Autodesk Fusion 360 part; units mm, degrees
(part 2 of 5)
sketch "rib pocket (9) (2)" plane through (0, 38.2, 0) normal (0, 1, 0) x (1, 0, 0) in component "Gripper finger L (TPU)"
  line L0 (-9.25, 2.8) -> (-0.75, 2.8)
  line L1 (-0.75, 2.8) -> (-4.75, 9.6313)
  line L2 (-4.75, 9.6313) -> (-9, 11.3821)
  line L3 (-9, 11.3821) -> (-13.25, 13.0725)
  line L4 (-13.25, 13.0725) -> (-9.25, 2.8)
extrude "rib pocket (10)'" cut sketch "rib pocket (9) (2)" along normal blind 22 bodies 12 in component "Gripper finger L (TPU)"
sketch "tongue slot (2)" plane through (0, 39.2, 0) normal (0, 1, 0) x (1, 0, 0) in component "Gripper finger L (TPU)"
  line L0 (-121, 13.7) -> (-107.8, 13.7)
  line L1 (-107.8, 13.7) -> (-107.8, 5.3)
  line L2 (-107.8, 5.3) -> (-121, 5.3)
  line L3 (-121, 5.3) -> (-121, 13.7)
extrude "tongue slot (1)'" cut sketch "tongue slot (2)" along normal blind 6.4 bodies 12 in component "Gripper finger L (TPU)"
ref_plane "WorkPlane3" through (0, 44.9, 0) normal (0, 1, 0) x (0, 0, 1) in component "Gripper finger L (TPU)"
sketch "screw hole (7)" plane through (0, 44.9, 0) normal (0, 1, 0) x (1, 0, 0) in component "Gripper finger L (TPU)"
  circle A0 centre (-114, 9.5) radius 1.7
extrude "screw hole (1)''" cut sketch "screw hole (7)" along normal blind 15.3 bodies 12 in component "Gripper finger L (TPU)"
ref_plane "WorkPlane1" through (0, 33, 0) normal (0, 1, 0) x (0, 0, 1) in component "Gripper head plate (printed)"
sketch "plate" plane through (0, 33, 0) normal (0, 1, 0) x (1, 0, 0) in component "Gripper head plate (printed)"
  line L0 (-128, -23) -> (-128.1363, -24.0353)
  line L1 (-128.1363, -24.0353) -> (-128.5359, -25)
  line L2 (-128.5359, -25) -> (-129.1716, -25.8284)
  line L3 (-129.1716, -25.8284) -> (-130, -26.4641)
  line L4 (-130, -26.4641) -> (-130.9647, -26.8637)
  line L5 (-130.9647, -26.8637) -> (-132, -27)
  line L6 (-132, -27) -> (-152, -27)
  line L7 (-152, -27) -> (-153.0353, -26.8637)
  line L8 (-153.0353, -26.8637) -> (-154, -26.4641)
  line L9 (-154, -26.4641) -> (-154.8284, -25.8284)
  line L10 (-154.8284, -25.8284) -> (-155.4641, -25)
  line L11 (-155.4641, -25) -> (-155.8637, -24.0353)
  line L12 (-155.8637, -24.0353) -> (-156, -23)
  line L13 (-156, -23) -> (-156, 23)
  line L14 (-156, 23) -> (-155.8637, 24.0353)
  line L15 (-155.8637, 24.0353) -> (-155.4641, 25)
  line L16 (-155.4641, 25) -> (-154.8284, 25.8284)
  line L17 (-154.8284, 25.8284) -> (-154, 26.4641)
  line L18 (-154, 26.4641) -> (-153.0353, 26.8637)
  line L19 (-153.0353, 26.8637) -> (-152, 27)
  line L20 (-152, 27) -> (-132, 27)
  line L21 (-132, 27) -> (-130.9647, 26.8637)
  line L22 (-130.9647, 26.8637) -> (-130, 26.4641)
  line L23 (-130, 26.4641) -> (-129.1716, 25.8284)
  line L24 (-129.1716, 25.8284) -> (-128.5359, 25)
  line L25 (-128.5359, 25) -> (-128.1363, 24.0353)
  line L26 (-128.1363, 24.0353) -> (-128, 23)
  line L27 (-128, 23) -> (-128, -23)
extrude "plate (1)" add sketch "plate" along normal blind 6 separate body makes body 13 in component "Gripper head plate (printed)"
sketch "spring lug" plane through (0, 33, 0) normal (0, 1, 0) x (1, 0, 0) in component "Gripper head plate (printed)"
  line L0 (-124, -30.5) -> (-124.0852, -31.147)
  line L1 (-124.0852, -31.147) -> (-124.3349, -31.75)
  line L2 (-124.3349, -31.75) -> (-124.7322, -32.2678)
  line L3 (-124.7322, -32.2678) -> (-125.25, -32.6651)
  line L4 (-125.25, -32.6651) -> (-125.853, -32.9148)
  line L5 (-125.853, -32.9148) -> (-126.5, -33)
  line L6 (-126.5, -33) -> (-130.5, -33)
  line L7 (-130.5, -33) -> (-131.147, -32.9148)
  line L8 (-131.147, -32.9148) -> (-131.75, -32.6651)
  line L9 (-131.75, -32.6651) -> (-132.2678, -32.2678)
  line L10 (-132.2678, -32.2678) -> (-132.6651, -31.75)
  line L11 (-132.6651, -31.75) -> (-132.9148, -31.147)
  line L12 (-132.9148, -31.147) -> (-133, -30.5)
  line L13 (-133, -30.5) -> (-133, -23.5)
  line L14 (-133, -23.5) -> (-132.9148, -22.853)
  line L15 (-132.9148, -22.853) -> (-132.6651, -22.25)
  line L16 (-132.6651, -22.25) -> (-132.2678, -21.7322)
  line L17 (-132.2678, -21.7322) -> (-131.75, -21.3349)
  line L18 (-131.75, -21.3349) -> (-131.147, -21.0852)
  line L19 (-131.147, -21.0852) -> (-130.5, -21)
  line L20 (-130.5, -21) -> (-126.5, -21)
  line L21 (-126.5, -21) -> (-125.853, -21.0852)
  line L22 (-125.853, -21.0852) -> (-125.25, -21.3349)
  line L23 (-125.25, -21.3349) -> (-124.7322, -21.7322)
  line L24 (-124.7322, -21.7322) -> (-124.3349, -22.25)
  line L25 (-124.3349, -22.25) -> (-124.0852, -22.853)
  line L26 (-124.0852, -22.853) -> (-124, -23.5)
  line L27 (-124, -23.5) -> (-124, -30.5)
extrude "spring lug (1)" add sketch "spring lug" along normal blind 6 separate body makes body 14 in component "Gripper head plate (printed)"
ref_plane "WorkPlane2" through (0, 0, 14.5) normal (0, 0, 1) x (1, 0, 0) in component "Gripper head plate (printed)"
sketch "tape tab" plane through (0, 0, 14.5) normal (0, 0, 1) x (1, 0, 0) in component "Gripper head plate (printed)"
  line L0 (-156, 21) -> (-150, 21)
  line L1 (-150, 21) -> (-150, 33.01)
  line L2 (-150, 33.01) -> (-156, 33.01)
  line L3 (-156, 33.01) -> (-156, 21)
extrude "tape tab (1)" add sketch "tape tab" along normal blind 2.2 separate body makes body 15 in component "Gripper head plate (printed)"
ref_plane "WorkPlane3" through (0, 0, -27) normal (0, 0, 1) x (1, 0, 0) in component "Gripper head plate (printed)"
sketch "damper hanger" plane through (0, 0, -27) normal (0, 0, 1) x (1, 0, 0) in component "Gripper head plate (printed)"
  line L0 (-147, 23.99) -> (-137, 23.99)
  line L1 (-137, 23.99) -> (-137, 33.01)
  line L2 (-137, 33.01) -> (-147, 33.01)
  line L3 (-147, 33.01) -> (-147, 23.99)
extrude "damper hanger (1)" add sketch "damper hanger" along normal blind 3.75 separate body makes body 16 in component "Gripper head plate (printed)"
ref_plane "WorkPlane4" through (0, 38.99, 0) normal (0, 1, 0) x (0, 0, 1) in component "Gripper head plate (printed)"
sketch "post" plane through (0, 38.99, 0) normal (0, 1, 0) x (1, 0, 0) in component "Gripper head plate (printed)"
  circle A0 centre (-151.5, -19) radius 3.5
extrude "post (1)" add sketch "post" along normal blind 6.82 separate body makes body 17 in component "Gripper head plate (printed)"
sketch "post (1)" plane through (0, 38.99, 0) normal (0, 1, 0) x (1, 0, 0) in component "Gripper head plate (printed)"
  circle A0 centre (-151.5, 19) radius 3.5
extrude "post (2)" add sketch "post (1)" along normal blind 6.82 separate body makes body 18 in component "Gripper head plate (printed)"
combine "Combine1'" operation add target body 13 tool bodies 14 in component "Gripper head plate (printed)"
combine "Combine2'" operation add target body 13 tool bodies 15 in component "Gripper head plate (printed)"
combine "Combine3'" operation add target body 13 tool bodies 16 in component "Gripper head plate (printed)"
combine "Combine4'" operation add target body 13 tool bodies 17 in component "Gripper head plate (printed)"
combine "Combine5'" operation add target body 13 tool bodies 18 in component "Gripper head plate (printed)"
ref_plane "WorkPlane5" through (0, 33.3, 0) normal (0, 1, 0) x (0, 0, 1) in component "Gripper head plate (printed)"
sketch "axle insert hole" plane through (0, 33.3, 0) normal (0, 1, 0) x (1, 0, 0) in component "Gripper head plate (printed)"
  circle A0 centre (-136, -9.5) radius 2
extrude "axle insert hole (1)" cut sketch "axle insert hole" along normal blind 6.7 bodies 13 in component "Gripper head plate (printed)"
sketch "axle insert hole (1)" plane through (0, 33.3, 0) normal (0, 1, 0) x (1, 0, 0) in component "Gripper head plate (printed)"
  circle A0 centre (-136, 9.5) radius 2
extrude "axle insert hole (2)" cut sketch "axle insert hole (1)" along normal blind 6.7 bodies 13 in component "Gripper head plate (printed)"
ref_plane "WorkPlane6" through (0, 32, 0) normal (0, 1, 0) x (0, 0, 1) in component "Gripper head plate (printed)"
sketch "carriage screw hole" plane through (0, 32, 0) normal (0, 1, 0) x (1, 0, 0) in component "Gripper head plate (printed)"
  circle A0 centre (-149, 10) radius 1.7
extrude "carriage screw hole (1)" cut sketch "carriage screw hole" along normal blind 8 bodies 13 in component "Gripper head plate (printed)"
ref_plane "WorkPlane7" through (0, 35.8, 0) normal (0, 1, 0) x (0, 0, 1) in component "Gripper head plate (printed)"
sketch "carriage screw counterbore" plane through (0, 35.8, 0) normal (0, 1, 0) x (1, 0, 0) in component "Gripper head plate (printed)"
  circle A0 centre (-149, 10) radius 3
extrude "carriage screw counterbore (1)" cut sketch "carriage screw counterbore" along normal blind 4.2 bodies 13 in component "Gripper head plate (printed)"
sketch "carriage screw hole (1)" plane through (0, 32, 0) normal (0, 1, 0) x (1, 0, 0) in component "Gripper head plate (printed)"
  circle A0 centre (-149, -10) radius 1.7
extrude "carriage screw hole (2)" cut sketch "carriage screw hole (1)" along normal blind 8 bodies 13 in component "Gripper head plate (printed)"
sketch "carriage screw counterbore (1)" plane through (0, 35.8, 0) normal (0, 1, 0) x (1, 0, 0) in component "Gripper head plate (printed)"
  circle A0 centre (-149, -10) radius 3
extrude "carriage screw counterbore (2)" cut sketch "carriage screw counterbore (1)" along normal blind 4.2 bodies 13 in component "Gripper head plate (printed)"
sketch "carriage screw hole (2)" plane through (0, 32, 0) normal (0, 1, 0) x (1, 0, 0) in component "Gripper head plate (printed)"
  circle A0 centre (-129, 10) radius 1.7
extrude "carriage screw hole (3)" cut sketch "carriage screw hole (2)" along normal blind 8 bodies 13 in component "Gripper head plate (printed)"
sketch "carriage screw counterbore (2)" plane through (0, 35.8, 0) normal (0, 1, 0) x (1, 0, 0) in component "Gripper head plate (printed)"
  circle A0 centre (-129, 10) radius 3
extrude "carriage screw counterbore (3)" cut sketch "carriage screw counterbore (2)" along normal blind 4.2 bodies 13 in component "Gripper head plate (printed)"
sketch "carriage screw hole (3)" plane through (0, 32, 0) normal (0, 1, 0) x (1, 0, 0) in component "Gripper head plate (printed)"
  circle A0 centre (-129, -10) radius 1.7
extrude "carriage screw hole (4)" cut sketch "carriage screw hole (3)" along normal blind 8 bodies 13 in component "Gripper head plate (printed)"
sketch "carriage screw counterbore (3)" plane through (0, 35.8, 0) normal (0, 1, 0) x (1, 0, 0) in component "Gripper head plate (printed)"
  circle A0 centre (-129, -10) radius 3
extrude "carriage screw counterbore (4)" cut sketch "carriage screw counterbore (3)" along normal blind 4.2 bodies 13 in component "Gripper head plate (printed)"
ref_plane "WorkPlane8" through (0, 40.1, 0) normal (0, 1, 0) x (0, 0, 1) in component "Gripper head plate (printed)"
sketch "post insert hole" plane through (0, 40.1, 0) normal (0, 1, 0) x (1, 0, 0) in component "Gripper head plate (printed)"
  circle A0 centre (-151.5, -19) radius 2
extrude "post insert hole (1)" cut sketch "post insert hole" along normal blind 6.7 bodies 13 in component "Gripper head plate (printed)"
sketch "post insert hole (1)" plane through (0, 40.1, 0) normal (0, 1, 0) x (1, 0, 0) in component "Gripper head plate (printed)"
  circle A0 centre (-151.5, 19) radius 2
extrude "post insert hole (2)" cut sketch "post insert hole (1)" along normal blind 6.7 bodies 13 in component "Gripper head plate (printed)"
sketch "spring pin hole" plane through (0, 32, 0) normal (0, 1, 0) x (1, 0, 0) in component "Gripper head plate (printed)"
  circle A0 centre (-127, -29.5) radius 1.6
extrude "spring pin hole (1)" cut sketch "spring pin hole" along normal blind 9 bodies 13 in component "Gripper head plate (printed)"
ref_plane "WorkPlane9" through (0, 0, -28) normal (0, 0, 1) x (1, 0, 0) in component "Gripper head plate (printed)"
sketch "lock pin hole" plane through (0, 0, -28) normal (0, 0, 1) x (1, 0, 0) in component "Gripper head plate (printed)"
  circle A0 centre (-142, 36) radius 2.8
extrude "lock pin hole (1)" cut sketch "lock pin hole" along normal blind 7.5 bodies 13 in component "Gripper head plate (printed)"
ref_plane "WorkPlane1" through (0, 45.8, 0) normal (0, 1, 0) x (0, 0, 1) in component "Gripper head lid (printed)"
sketch "lid" plane through (0, 45.8, 0) normal (0, 1, 0) x (1, 0, 0) in component "Gripper head lid (printed)"
  line L0 (-128, -23) -> (-128.1363, -24.0353)
  line L1 (-128.1363, -24.0353) -> (-128.5359, -25)
  line L2 (-128.5359, -25) -> (-129.1716, -25.8284)
  line L3 (-129.1716, -25.8284) -> (-130, -26.4641)
  line L4 (-130, -26.4641) -> (-130.9647, -26.8637)
  line L5 (-130.9647, -26.8637) -> (-132, -27)
  line L6 (-132, -27) -> (-152, -27)
  line L7 (-152, -27) -> (-153.0353, -26.8637)
  line L8 (-153.0353, -26.8637) -> (-154, -26.4641)
  line L9 (-154, -26.4641) -> (-154.8284, -25.8284)
  line L10 (-154.8284, -25.8284) -> (-155.4641, -25)
  line L11 (-155.4641, -25) -> (-155.8637, -24.0353)
  line L12 (-155.8637, -24.0353) -> (-156, -23)
  line L13 (-156, -23) -> (-156, 23)
  line L14 (-156, 23) -> (-155.8637, 24.0353)
  line L15 (-155.8637, 24.0353) -> (-155.4641, 25)
  line L16 (-155.4641, 25) -> (-154.8284, 25.8284)
  line L17 (-154.8284, 25.8284) -> (-154, 26.4641)
  line L18 (-154, 26.4641) -> (-153.0353, 26.8637)
  line L19 (-153.0353, 26.8637) -> (-152, 27)
  line L20 (-152, 27) -> (-132, 27)
  line L21 (-132, 27) -> (-130.9647, 26.8637)
  line L22 (-130.9647, 26.8637) -> (-130, 26.4641)
  line L23 (-130, 26.4641) -> (-129.1716, 25.8284)
  line L24 (-129.1716, 25.8284) -> (-128.5359, 25)
  line L25 (-128.5359, 25) -> (-128.1363, 24.0353)
  line L26 (-128.1363, 24.0353) -> (-128, 23)
  line L27 (-128, 23) -> (-128, -23)
extrude "lid (1)" add sketch "lid" along normal blind 4 separate body makes body 19 in component "Gripper head lid (printed)"
ref_plane "WorkPlane2" through (0, 44.8, 0) normal (0, 1, 0) x (0, 0, 1) in component "Gripper head lid (printed)"
sketch "axle hole" plane through (0, 44.8, 0) normal (0, 1, 0) x (1, 0, 0) in component "Gripper head lid (printed)"
  circle A0 centre (-136, -9.5) radius 1.7
extrude "axle hole (1)" cut sketch "axle hole" along normal blind 6 bodies 19 in component "Gripper head lid (printed)"
sketch "axle hole (1)" plane through (0, 44.8, 0) normal (0, 1, 0) x (1, 0, 0) in component "Gripper head lid (printed)"
  circle A0 centre (-136, 9.5) radius 1.7
extrude "axle hole (2)" cut sketch "axle hole (1)" along normal blind 6 bodies 19 in component "Gripper head lid (printed)"
sketch "screw hole (8)" plane through (0, 44.8, 0) normal (0, 1, 0) x (1, 0, 0) in component "Gripper head lid (printed)"
  circle A0 centre (-151.5, -19) radius 1.7
extrude "screw hole (1)'''" cut sketch "screw hole (8)" along normal blind 6 bodies 19 in component "Gripper head lid (printed)"
sketch "screw hole (1) (2)" plane through (0, 44.8, 0) normal (0, 1, 0) x (1, 0, 0) in component "Gripper head lid (printed)"
  circle A0 centre (-151.5, 19) radius 1.7
extrude "screw hole (2)'" cut sketch "screw hole (1) (2)" along normal blind 6 bodies 19 in component "Gripper head lid (printed)"
ref_plane "WorkPlane1" through (0, 39.4, 0) normal (0, 1, 0) x (0, 0, 1) in component "Gripper gear R (printed)"
sketch "gear" plane through (0, 39.4, 0) normal (0, 1, 0) x (1, 0, 0) in component "Gripper gear R (printed)"
  line L0 (-136.7821, -1.2872) -> (-136.8463, -0.6131)
  line L1 (-136.8463, -0.6131) -> (-136.8283, -0.3482)
  line L2 (-136.8283, -0.3482) -> (-136.7729, -0.0803)
  line L3 (-136.7729, -0.0803) -> (-136.6912, 0.1889)
  line L4 (-136.6912, 0.1889) -> (-136.5867, 0.4584)
  line L5 (-136.5867, 0.4584) -> (-136.4615, 0.7274)
  line L6 (-136.4615, 0.7274) -> (-136.3166, 0.9952)
  line L7 (-136.3166, 0.9952) -> (-135.6834, 0.9952)
  line L8 (-135.6834, 0.9952) -> (-135.5385, 0.7274)
  line L9 (-135.5385, 0.7274) -> (-135.4133, 0.4584)
  line L10 (-135.4133, 0.4584) -> (-135.3088, 0.1889)
  line L11 (-135.3088, 0.1889) -> (-135.2271, -0.0803)
  line L12 (-135.2271, -0.0803) -> (-135.1717, -0.3482)
  line L13 (-135.1717, -0.3482) -> (-135.1537, -0.6131)
  line L14 (-135.1537, -0.6131) -> (-135.2179, -1.2872)
  line L15 (-135.2179, -1.2872) -> (-134.8334, -1.3329)
  line L16 (-134.8334, -1.3329) -> (-134.4515, -1.3966)
  line L17 (-134.4515, -1.3966) -> (-134.073, -1.4782)
  line L18 (-134.073, -1.4782) -> (-133.9149, -0.8198)
  line L19 (-133.9149, -0.8198) -> (-133.8119, -0.5751)
  line L20 (-133.8119, -0.5751) -> (-133.6724, -0.3397)
  line L21 (-133.6724, -0.3397) -> (-133.5077, -0.1116)
  line L22 (-133.5077, -0.1116) -> (-133.3214, 0.1094)
  line L23 (-133.3214, 0.1094) -> (-133.1156, 0.3231)
  line L24 (-133.1156, 0.3231) -> (-132.8917, 0.5294)
  line L25 (-132.8917, 0.5294) -> (-132.2928, 0.3238)
  line L26 (-132.2928, 0.3238) -> (-132.2427, 0.0235)
  line L27 (-132.2427, 0.0235) -> (-132.2116, -0.2717)
  line L28 (-132.2116, -0.2717) -> (-132.2003, -0.5605)
  line L29 (-132.2003, -0.5605) -> (-132.2104, -0.8416)
  line L30 (-132.2104, -0.8416) -> (-132.245, -1.113)
  line L31 (-132.245, -1.113) -> (-132.314, -1.3694)
  line L32 (-132.314, -1.3694) -> (-132.5935, -1.9861)
  line L33 (-132.5935, -1.9861) -> (-132.2448, -2.1542)
  line L34 (-132.2448, -2.1542) -> (-131.9043, -2.3385)
  line L35 (-131.9043, -2.3385) -> (-131.5728, -2.5385)
  line L36 (-131.5728, -2.5385) -> (-131.2094, -1.9672)
  line L37 (-131.2094, -1.9672) -> (-131.0325, -1.7692)
  line L38 (-131.0325, -1.7692) -> (-130.8242, -1.5918)
  line L39 (-130.8242, -1.5918) -> (-130.5944, -1.4296)
  line L40 (-130.5944, -1.4296) -> (-130.3464, -1.281)
  line L41 (-130.3464, -1.281) -> (-130.0823, -1.1457)
  line L42 (-130.0823, -1.1457) -> (-129.8035, -1.0233)
  line L43 (-129.8035, -1.0233) -> (-129.3039, -1.4123)
  line L44 (-129.3039, -1.4123) -> (-129.354, -1.7125)
  line L45 (-129.354, -1.7125) -> (-129.4204, -2.0018)
  line L46 (-129.4204, -2.0018) -> (-129.5035, -2.2786)
  line L47 (-129.5035, -2.2786) -> (-129.6044, -2.5412)
  line L48 (-129.6044, -2.5412) -> (-129.7252, -2.7867)
  line L49 (-129.7252, -2.7867) -> (-129.8737, -3.0068)
  line L50 (-129.8737, -3.0068) -> (-130.3384, -3.4993)
  line L51 (-130.3384, -3.4993) -> (-130.0631, -3.7715)
  line L52 (-130.0631, -3.7715) -> (-129.8008, -4.0564)
  line L53 (-129.8008, -4.0564) -> (-129.5523, -4.3532)
  line L54 (-129.5523, -4.3532) -> (-129.0231, -3.9308)
  line L55 (-129.0231, -3.9308) -> (-128.7914, -3.801)
  line L56 (-128.7914, -3.801) -> (-128.5369, -3.7008)
  line L57 (-128.5369, -3.7008) -> (-128.2668, -3.622)
  line L58 (-128.2668, -3.622) -> (-127.984, -3.5621)
  line L59 (-127.984, -3.5621) -> (-127.6903, -3.5198)
  line L60 (-127.6903, -3.5198) -> (-127.3869, -3.4946)
  line L61 (-127.3869, -3.4946) -> (-127.0406, -4.0247)
  line L62 (-127.0406, -4.0247) -> (-127.1855, -4.2924)
  line L63 (-127.1855, -4.2924) -> (-127.3422, -4.5444)
  line L64 (-127.3422, -4.5444) -> (-127.5107, -4.7793)
  line L65 (-127.5107, -4.7793) -> (-127.6914, -4.9949)
  line L66 (-127.6914, -4.9949) -> (-127.8853, -5.1879)
  line L67 (-127.8853, -5.1879) -> (-128.0973, -5.3479)
  line L68 (-128.0973, -5.3479) -> (-128.6967, -5.6628)
  line L69 (-128.6967, -5.6628) -> (-128.5247, -6.0096)
  line L70 (-128.5247, -6.0096) -> (-128.3692, -6.3642)
  line L71 (-128.3692, -6.3642) -> (-128.2305, -6.7257)
  line L72 (-128.2305, -6.7257) -> (-127.5928, -6.498)
  line L73 (-127.5928, -6.498) -> (-127.3316, -6.4504)
  line L74 (-127.3316, -6.4504) -> (-127.0582, -6.4383)
  line L75 (-127.0582, -6.4383) -> (-126.7772, -6.4515)
  line L76 (-126.7772, -6.4515) -> (-126.4903, -6.4866)
  line L77 (-126.4903, -6.4866) -> (-126.1988, -6.542)
  line L78 (-126.1988, -6.542) -> (-125.9036, -6.6167)
  line L79 (-125.9036, -6.6167) -> (-125.7482, -7.2305)
  line L80 (-125.7482, -7.2305) -> (-125.9722, -7.4366)
  line L81 (-125.9722, -7.4366) -> (-126.2023, -7.6241)
  line L82 (-126.2023, -7.6241) -> (-126.4379, -7.7915)
  line L83 (-126.4379, -7.7915) -> (-126.6788, -7.9368)
  line L84 (-126.6788, -7.9368) -> (-126.9249, -8.0563)
  line L85 (-126.9249, -8.0563) -> (-127.1773, -8.1388)
  line L86 (-127.1773, -8.1388) -> (-127.8465, -8.2421)
  line L87 (-127.8465, -8.2421) -> (-127.7964, -8.626)
  line L88 (-127.7964, -8.626) -> (-127.7645, -9.0118)
  line L89 (-127.7645, -9.0118) -> (-127.7506, -9.3988)
  line L90 (-127.7506, -9.3988) -> (-127.0736, -9.3904)
  line L91 (-127.0736, -9.3904) -> (-126.811, -9.4303)
  line L92 (-126.811, -9.4303) -> (-126.5486, -9.5076)
  line L93 (-126.5486, -9.5076) -> (-126.2871, -9.6113)
  line L94 (-126.2871, -9.6113) -> (-126.0271, -9.7376)
  line L95 (-126.0271, -9.7376) -> (-125.7694, -9.8847)
  line L96 (-125.7694, -9.8847) -> (-125.5145, -10.0512)
  line L97 (-125.5145, -10.0512) -> (-125.5668, -10.6822)
  line L98 (-125.5668, -10.6822) -> (-125.8456, -10.8045)
  line L99 (-125.8456, -10.8045) -> (-126.124, -10.9071)
  line L100 (-126.124, -10.9071) -> (-126.4012, -10.9889)
  line L101 (-126.4012, -10.9889) -> (-126.6763, -11.0481)
  line L102 (-126.6763, -11.0481) -> (-126.9478, -11.0812)
  line L103 (-126.9478, -11.0812) -> (-127.2134, -11.0773)
  line L104 (-127.2134, -11.0773) -> (-127.8798, -10.9577)
  line L105 (-127.8798, -10.9577) -> (-127.9571, -11.337)
  line L106 (-127.9571, -11.337) -> (-128.0522, -11.7124)
  line L107 (-128.0522, -11.7124) -> (-128.1647, -12.0828)
  line L108 (-128.1647, -12.0828) -> (-127.5217, -12.2948)
  line L109 (-127.5217, -12.2948) -> (-127.2863, -12.4177)
  line L110 (-127.2863, -12.4177) -> (-127.0632, -12.5761)
  line L111 (-127.0632, -12.5761) -> (-126.8495, -12.759)
  line L112 (-126.8495, -12.759) -> (-126.6447, -12.963)
  line L113 (-126.6447, -12.963) -> (-126.4486, -13.1857)
  line L114 (-126.4486, -13.1857) -> (-126.2616, -13.4259)
  line L115 (-126.2616, -13.4259) -> (-126.5159, -14.0058)
  line L116 (-126.5159, -14.0058) -> (-126.8193, -14.0309)
  line L117 (-126.8193, -14.0309) -> (-127.116, -14.0376)
  line L118 (-127.116, -14.0376) -> (-127.4048, -14.0249)
  line L119 (-127.4048, -14.0249) -> (-127.6841, -13.9917)
  line L120 (-127.6841, -13.9917) -> (-127.9517, -13.9348)
  line L121 (-127.9517, -13.9348) -> (-128.2016, -13.8449)
  line L122 (-128.2016, -13.8449) -> (-128.7931, -13.5153)
  line L123 (-128.7931, -13.5153) -> (-128.9894, -13.849)
  line L124 (-128.9894, -13.849) -> (-129.2012, -14.1731)
  line L125 (-129.2012, -14.1731) -> (-129.4279, -14.487)
  line L126 (-129.4279, -14.487) -> (-128.8885, -14.8963)
  line L127 (-128.8885, -14.8963) -> (-128.7058, -15.0889)
  line L128 (-128.7058, -15.0889) -> (-128.5462, -15.3112)
  line L129 (-128.5462, -15.3112) -> (-128.4035, -15.5536)
  line L130 (-128.4035, -15.5536) -> (-128.276, -15.813)
  line L131 (-128.276, -15.813) -> (-128.1629, -16.0874)
  line L132 (-128.1629, -16.0874) -> (-128.064, -16.3753)
  line L133 (-128.064, -16.3753) -> (-128.4928, -16.8412)
  line L134 (-128.4928, -16.8412) -> (-128.788, -16.7664)
  line L135 (-128.788, -16.7664) -> (-129.0707, -16.6763)
  line L136 (-129.0707, -16.6763) -> (-129.3397, -16.5706)
  line L137 (-129.3397, -16.5706) -> (-129.5931, -16.4485)
  line L138 (-129.5931, -16.4485) -> (-129.8278, -16.3078)
  line L139 (-129.8278, -16.3078) -> (-130.0349, -16.1416)
  line L140 (-130.0349, -16.1416) -> (-130.4873, -15.6378)
  line L141 (-130.4873, -15.6378) -> (-130.7814, -15.8897)
  line L142 (-130.7814, -15.8897) -> (-131.0869, -16.1275)
  line L143 (-131.0869, -16.1275) -> (-131.4033, -16.3507)
  line L144 (-131.4033, -16.3507) -> (-131.026, -16.913)
  line L145 (-131.026, -16.913) -> (-130.9157, -17.1546)
  line L146 (-130.9157, -17.1546) -> (-130.837, -17.4165)
  line L147 (-130.837, -17.4165) -> (-130.7807, -17.6922)
  line L148 (-130.7807, -17.6922) -> (-130.7443, -17.9789)
  line L149 (-130.7443, -17.9789) -> (-130.7264, -18.2751)
  line L150 (-130.7264, -18.2751) -> (-130.7264, -18.5796)
  line L151 (-130.7264, -18.5796) -> (-131.2833, -18.881)
  line L152 (-131.2833, -18.881) -> (-131.5381, -18.7144)
  line L153 (-131.5381, -18.7144) -> (-131.7763, -18.5374)
  line L154 (-131.7763, -18.5374) -> (-131.9964, -18.3501)
  line L155 (-131.9964, -18.3501) -> (-132.1964, -18.1523)
  line L156 (-132.1964, -18.1523) -> (-132.3727, -17.943)
  line L157 (-132.3727, -17.943) -> (-132.5146, -17.7186)
  line L158 (-132.5146, -17.7186) -> (-132.779, -17.0952)
  line L159 (-132.779, -17.0952) -> (-133.1389, -17.238)
  line L160 (-133.1389, -17.238) -> (-133.5051, -17.3637)
  line L161 (-133.5051, -17.3637) -> (-133.8767, -17.4721)
  line L162 (-133.8767, -17.4721) -> (-133.7025, -18.1264)
  line L163 (-133.7025, -18.1264) -> (-133.6766, -18.3907)
  line L164 (-133.6766, -18.3907) -> (-133.6872, -18.664)
  line L165 (-133.6872, -18.664) -> (-133.7235, -18.943)
  line L166 (-133.7235, -18.943) -> (-133.7822, -19.226)
  line L167 (-133.7822, -19.226) -> (-133.8615, -19.512)
  line L168 (-133.8615, -19.512) -> (-133.9603, -19.8)
  line L169 (-133.9603, -19.8) -> (-134.5848, -19.9042)
  line L170 (-134.5848, -19.9042) -> (-134.7718, -19.6639)
  line L171 (-134.7718, -19.6639) -> (-134.9396, -19.4192)
  line L172 (-134.9396, -19.4192) -> (-135.087, -19.1705)
  line L173 (-135.087, -19.1705) -> (-135.2119, -18.9185)
  line L174 (-135.2119, -18.9185) -> (-135.3107, -18.6633)
  line L175 (-135.3107, -18.6633) -> (-135.372, -18.405)
  line L176 (-135.372, -18.405) -> (-135.4197, -17.7296)
  line L177 (-135.4197, -17.7296) -> (-135.8064, -17.7477)
  line L178 (-135.8064, -17.7477) -> (-136.1936, -17.7477)
  line L179 (-136.1936, -17.7477) -> (-136.5803, -17.7296)
  line L180 (-136.5803, -17.7296) -> (-136.628, -18.405)
  line L181 (-136.628, -18.405) -> (-136.6893, -18.6633)
  line L182 (-136.6893, -18.6633) -> (-136.7881, -18.9185)
  line L183 (-136.7881, -18.9185) -> (-136.913, -19.1705)
  line L184 (-136.913, -19.1705) -> (-137.0604, -19.4192)
  line L185 (-137.0604, -19.4192) -> (-137.2282, -19.6639)
  line L186 (-137.2282, -19.6639) -> (-137.4152, -19.9042)
  line L187 (-137.4152, -19.9042) -> (-138.0397, -19.8)
  line L188 (-138.0397, -19.8) -> (-138.1385, -19.512)
  line L189 (-138.1385, -19.512) -> (-138.2178, -19.226)
  line L190 (-138.2178, -19.226) -> (-138.2765, -18.943)
  line L191 (-138.2765, -18.943) -> (-138.3128, -18.664)
  line L192 (-138.3128, -18.664) -> (-138.3234, -18.3907)
  line L193 (-138.3234, -18.3907) -> (-138.2975, -18.1264)
  line L194 (-138.2975, -18.1264) -> (-138.1233, -17.4721)
  line L195 (-138.1233, -17.4721) -> (-138.4949, -17.3637)
  line L196 (-138.4949, -17.3637) -> (-138.8611, -17.238)
  line L197 (-138.8611, -17.238) -> (-139.221, -17.0952)
  line L198 (-139.221, -17.0952) -> (-139.4854, -17.7186)
  line L199 (-139.4854, -17.7186) -> (-139.6273, -17.943)
  line L200 (-139.6273, -17.943) -> (-139.8036, -18.1523)
  line L201 (-139.8036, -18.1523) -> (-140.0036, -18.3501)
  line L202 (-140.0036, -18.3501) -> (-140.2237, -18.5374)
  line L203 (-140.2237, -18.5374) -> (-140.4619, -18.7144)
  line L204 (-140.4619, -18.7144) -> (-140.7167, -18.881)
  line L205 (-140.7167, -18.881) -> (-141.2736, -18.5796)
  line L206 (-141.2736, -18.5796) -> (-141.2736, -18.2751)
  line L207 (-141.2736, -18.2751) -> (-141.2557, -17.9789)
  line L208 (-141.2557, -17.9789) -> (-141.2193, -17.6922)
  line L209 (-141.2193, -17.6922) -> (-141.163, -17.4165)
  line L210 (-141.163, -17.4165) -> (-141.0843, -17.1546)
  line L211 (-141.0843, -17.1546) -> (-140.974, -16.913)
  line L212 (-140.974, -16.913) -> (-140.5967, -16.3507)
  line L213 (-140.5967, -16.3507) -> (-140.9131, -16.1275)
  line L214 (-140.9131, -16.1275) -> (-141.2186, -15.8897)
  line L215 (-141.2186, -15.8897) -> (-141.5127, -15.6378)
  line L216 (-141.5127, -15.6378) -> (-141.9651, -16.1416)
  line L217 (-141.9651, -16.1416) -> (-142.1722, -16.3078)
  line L218 (-142.1722, -16.3078) -> (-142.4069, -16.4485)
  line L219 (-142.4069, -16.4485) -> (-142.6603, -16.5706)
  line L220 (-142.6603, -16.5706) -> (-142.9293, -16.6763)
  line L221 (-142.9293, -16.6763) -> (-143.212, -16.7664)
  line L222 (-143.212, -16.7664) -> (-143.5072, -16.8412)
  line L223 (-143.5072, -16.8412) -> (-143.936, -16.3753)
  line L224 (-143.936, -16.3753) -> (-143.8371, -16.0874)
  line L225 (-143.8371, -16.0874) -> (-143.724, -15.813)
  line L226 (-143.724, -15.813) -> (-143.5965, -15.5536)
  line L227 (-143.5965, -15.5536) -> (-143.4538, -15.3112)
  line L228 (-143.4538, -15.3112) -> (-143.2942, -15.0889)
  line L229 (-143.2942, -15.0889) -> (-143.1115, -14.8963)
  line L230 (-143.1115, -14.8963) -> (-142.5721, -14.487)
  line L231 (-142.5721, -14.487) -> (-142.7988, -14.1731)
  line L232 (-142.7988, -14.1731) -> (-143.0106, -13.849)
  line L233 (-143.0106, -13.849) -> (-143.2069, -13.5153)
  line L234 (-143.2069, -13.5153) -> (-143.7984, -13.8449)
  line L235 (-143.7984, -13.8449) -> (-144.0483, -13.9348)
  line L236 (-144.0483, -13.9348) -> (-144.3159, -13.9917)
  line L237 (-144.3159, -13.9917) -> (-144.5952, -14.0249)
  line L238 (-144.5952, -14.0249) -> (-144.884, -14.0376)
  line L239 (-144.884, -14.0376) -> (-145.1807, -14.0309)
  line L240 (-145.1807, -14.0309) -> (-145.4841, -14.0058)
  line L241 (-145.4841, -14.0058) -> (-145.7384, -13.4259)
  line L242 (-145.7384, -13.4259) -> (-145.5514, -13.1857)
  line L243 (-145.5514, -13.1857) -> (-145.3553, -12.963)
  line L244 (-145.3553, -12.963) -> (-145.1505, -12.759)
  line L245 (-145.1505, -12.759) -> (-144.9368, -12.5761)
  line L246 (-144.9368, -12.5761) -> (-144.7137, -12.4177)
  line L247 (-144.7137, -12.4177) -> (-144.4783, -12.2948)
  line L248 (-144.4783, -12.2948) -> (-143.8353, -12.0828)
  line L249 (-143.8353, -12.0828) -> (-143.9478, -11.7124)
  line L250 (-143.9478, -11.7124) -> (-144.0429, -11.337)
  line L251 (-144.0429, -11.337) -> (-144.1202, -10.9577)
  line L252 (-144.1202, -10.9577) -> (-144.7866, -11.0773)
  line L253 (-144.7866, -11.0773) -> (-145.0522, -11.0812)
  line L254 (-145.0522, -11.0812) -> (-145.3237, -11.0481)
  line L255 (-145.3237, -11.0481) -> (-145.5988, -10.9889)
  line L256 (-145.5988, -10.9889) -> (-145.876, -10.9071)
  line L257 (-145.876, -10.9071) -> (-146.1544, -10.8045)
  line L258 (-146.1544, -10.8045) -> (-146.4332, -10.6822)
  line L259 (-146.4332, -10.6822) -> (-146.4855, -10.0512)
  line L260 (-146.4855, -10.0512) -> (-146.2306, -9.8847)
  line L261 (-146.2306, -9.8847) -> (-145.9729, -9.7376)
  line L262 (-145.9729, -9.7376) -> (-145.7129, -9.6113)
  line L263 (-145.7129, -9.6113) -> (-145.4514, -9.5076)
  line L264 (-145.4514, -9.5076) -> (-145.189, -9.4303)
  line L265 (-145.189, -9.4303) -> (-144.9264, -9.3904)
  line L266 (-144.9264, -9.3904) -> (-144.2494, -9.3988)
  line L267 (-144.2494, -9.3988) -> (-144.2355, -9.0118)
  line L268 (-144.2355, -9.0118) -> (-144.2036, -8.626)
  line L269 (-144.2036, -8.626) -> (-144.1535, -8.2421)
  line L270 (-144.1535, -8.2421) -> (-144.8227, -8.1388)
  line L271 (-144.8227, -8.1388) -> (-145.0751, -8.0563)
  line L272 (-145.0751, -8.0563) -> (-145.3212, -7.9368)
  line L273 (-145.3212, -7.9368) -> (-145.5621, -7.7915)
  line L274 (-145.5621, -7.7915) -> (-145.7977, -7.6241)
  line L275 (-145.7977, -7.6241) -> (-146.0278, -7.4366)
  line L276 (-146.0278, -7.4366) -> (-146.2518, -7.2305)
  line L277 (-146.2518, -7.2305) -> (-146.0964, -6.6167)
  line L278 (-146.0964, -6.6167) -> (-145.8012, -6.542)
  line L279 (-145.8012, -6.542) -> (-145.5097, -6.4866)
  line L280 (-145.5097, -6.4866) -> (-145.2228, -6.4515)
  line L281 (-145.2228, -6.4515) -> (-144.9418, -6.4383)
  line L282 (-144.9418, -6.4383) -> (-144.6684, -6.4504)
  line L283 (-144.6684, -6.4504) -> (-144.4072, -6.498)
  line L284 (-144.4072, -6.498) -> (-143.7695, -6.7257)
  line L285 (-143.7695, -6.7257) -> (-143.6308, -6.3642)
  line L286 (-143.6308, -6.3642) -> (-143.4753, -6.0096)
  line L287 (-143.4753, -6.0096) -> (-143.3033, -5.6628)
  line L288 (-143.3033, -5.6628) -> (-143.9027, -5.3479)
  line L289 (-143.9027, -5.3479) -> (-144.1147, -5.1879)
  line L290 (-144.1147, -5.1879) -> (-144.3086, -4.9949)
  line L291 (-144.3086, -4.9949) -> (-144.4893, -4.7793)
  line L292 (-144.4893, -4.7793) -> (-144.6578, -4.5444)
  line L293 (-144.6578, -4.5444) -> (-144.8145, -4.2924)
  line L294 (-144.8145, -4.2924) -> (-144.9594, -4.0247)
  line L295 (-144.9594, -4.0247) -> (-144.6131, -3.4946)
  line L296 (-144.6131, -3.4946) -> (-144.3097, -3.5198)
  line L297 (-144.3097, -3.5198) -> (-144.016, -3.5621)
  line L298 (-144.016, -3.5621) -> (-143.7332, -3.622)
  line L299 (-143.7332, -3.622) -> (-143.4631, -3.7008)
  line L300 (-143.4631, -3.7008) -> (-143.2086, -3.801)
  line L301 (-143.2086, -3.801) -> (-142.9769, -3.9308)
  line L302 (-142.9769, -3.9308) -> (-142.4477, -4.3532)
  line L303 (-142.4477, -4.3532) -> (-142.1992, -4.0564)
  line L304 (-142.1992, -4.0564) -> (-141.9369, -3.7715)
  line L305 (-141.9369, -3.7715) -> (-141.6616, -3.4993)
  line L306 (-141.6616, -3.4993) -> (-142.1263, -3.0068)
  line L307 (-142.1263, -3.0068) -> (-142.2748, -2.7867)
  line L308 (-142.2748, -2.7867) -> (-142.3956, -2.5412)
  line L309 (-142.3956, -2.5412) -> (-142.4965, -2.2786)
  line L310 (-142.4965, -2.2786) -> (-142.5796, -2.0018)
  line L311 (-142.5796, -2.0018) -> (-142.646, -1.7125)
  line L312 (-142.646, -1.7125) -> (-142.6961, -1.4123)
  line L313 (-142.6961, -1.4123) -> (-142.1965, -1.0233)
  line L314 (-142.1965, -1.0233) -> (-141.9177, -1.1457)
  line L315 (-141.9177, -1.1457) -> (-141.6536, -1.281)
  line L316 (-141.6536, -1.281) -> (-141.4056, -1.4296)
  line L317 (-141.4056, -1.4296) -> (-141.1758, -1.5918)
  line L318 (-141.1758, -1.5918) -> (-140.9675, -1.7692)
  line L319 (-140.9675, -1.7692) -> (-140.7906, -1.9672)
  line L320 (-140.7906, -1.9672) -> (-140.4272, -2.5385)
  line L321 (-140.4272, -2.5385) -> (-140.0957, -2.3385)
  line L322 (-140.0957, -2.3385) -> (-139.7552, -2.1542)
  line L323 (-139.7552, -2.1542) -> (-139.4065, -1.9861)
  line L324 (-139.4065, -1.9861) -> (-139.686, -1.3694)
  line L325 (-139.686, -1.3694) -> (-139.755, -1.113)
  line L326 (-139.755, -1.113) -> (-139.7896, -0.8416)
  line L327 (-139.7896, -0.8416) -> (-139.7997, -0.5605)
  line L328 (-139.7997, -0.5605) -> (-139.7884, -0.2717)
  line L329 (-139.7884, -0.2717) -> (-139.7573, 0.0235)
  line L330 (-139.7573, 0.0235) -> (-139.7072, 0.3238)
  line L331 (-139.7072, 0.3238) -> (-139.1083, 0.5294)
  line L332 (-139.1083, 0.5294) -> (-138.8844, 0.3231)
  line L333 (-138.8844, 0.3231) -> (-138.6786, 0.1094)
  line L334 (-138.6786, 0.1094) -> (-138.4923, -0.1116)
  line L335 (-138.4923, -0.1116) -> (-138.3276, -0.3397)
  line L336 (-138.3276, -0.3397) -> (-138.1881, -0.5751)
  line L337 (-138.1881, -0.5751) -> (-138.0851, -0.8198)
  line L338 (-138.0851, -0.8198) -> (-137.927, -1.4782)
  line L339 (-137.927, -1.4782) -> (-137.5485, -1.3966)
  line L340 (-137.5485, -1.3966) -> (-137.1666, -1.3329)
  line L341 (-137.1666, -1.3329) -> (-136.7821, -1.2872)
extrude "gear (1)" add sketch "gear" along normal blind 6 separate body makes body 20 in component "Gripper gear R (printed)"
sketch "finger tongue" plane through (0, 39.4, 0) normal (0, 1, 0) x (1, 0, 0) in component "Gripper gear R (printed)"
  line L0 (-131, -5.5) -> (-108, -5.5)
  line L1 (-108, -5.5) -> (-108, -13.5)
  line L2 (-108, -13.5) -> (-131, -13.5)
  line L3 (-131, -13.5) -> (-131, -5.5)
extrude "finger tongue (1)" add sketch "finger tongue" along normal blind 6 separate body makes body 21 in component "Gripper gear R (printed)"
sketch "drive arm" plane through (0, 39.4, 0) normal (0, 1, 0) x (1, 0, 0) in component "Gripper gear R (printed)"
  line L0 (-141, -14.5) -> (-131, -14.5)
  line L1 (-131, -14.5) -> (-131, -42.5)
  line L2 (-131, -42.5) -> (-141, -42.5)
  line L3 (-141, -42.5) -> (-141, -14.5)
extrude "drive arm (1)" add sketch "drive arm" along normal blind 6 separate body makes body 22 in component "Gripper gear R (printed)"
combine "Combine1''" operation add target body 20 tool bodies 21 in component "Gripper gear R (printed)"
combine "Combine2''" operation add target body 20 tool bodies 22 in component "Gripper gear R (printed)"
ref_plane "WorkPlane2" through (0, 38.4, 0) normal (0, 1, 0) x (0, 0, 1) in component "Gripper gear R (printed)"
sketch "drive pin hole" plane through (0, 38.4, 0) normal (0, 1, 0) x (1, 0, 0) in component "Gripper gear R (printed)"
  circle A0 centre (-136, -37.5) radius 2.15
extrude "drive pin hole (1)" cut sketch "drive pin hole" along normal blind 9 bodies 20 in component "Gripper gear R (printed)"
sketch "axle bore" plane through (0, 38.4, 0) normal (0, 1, 0) x (1, 0, 0) in component "Gripper gear R (printed)"
  circle A0 centre (-136, -9.5) radius 1.7
extrude "axle bore (1)" cut sketch "axle bore" along normal blind 8 bodies 20 in component "Gripper gear R (printed)"
sketch "finger insert hole" plane through (0, 38.4, 0) normal (0, 1, 0) x (1, 0, 0) in component "Gripper gear R (printed)"
  circle A0 centre (-114, -9.5) radius 2
extrude "finger insert hole (1)" cut sketch "finger insert hole" along normal blind 8 bodies 20 in component "Gripper gear R (printed)"
ref_plane "WorkPlane1" through (0, 39.4, 0) normal (0, 1, 0) x (0, 0, 1) in component "Gripper gear L (printed)"